Autodesk Fusion 360 part; units mm, degrees
(part 2 of 2)
sketch "Sketch14" plane through (0, 0, 2.5) normal (0, 0, 1) x (1, 0, 0)
  circle A0 centre (35, 68) radius 2.5
  line L0 (125, 20) -> (125, 40)
  line L1 (125, 40) -> (145, 40)
  line L2 (145, 40) -> (145, 20)
  line L3 (145, 20) -> (125, 20)
  line L4 (9.0092, 116.9631) -> (-2, 103.2016)
  line L5 (-2, 103.2016) -> (-2, 11.7984)
  line L6 (-2, 11.7984) -> (9.0388, -2)
  line L7 (9.0388, -2) -> (145.9612, -2)
  line L8 (145.9612, -2) -> (157, 11.7984)
  line L9 (157, 11.7984) -> (157, 103.2016)
  line L10 (157, 103.2016) -> (145.9908, 116.9631)
  spline S0 degree 3 poles (145.9908, 116.9631) (145.6863, 116.9749) (145.3819, 116.9867) (145.0774, 116.9985) (138.5067, 117.2531) (133.3735, 117.448) (128.9839, 117.6117) (123.3639, 117.8212) (118.9847, 117.9786) (115.2269, 118.109) (110.0914, 118.2873) (106.1355, 118.4146) (102.7172, 118.5165) (98.1859, 118.6516) (94.6262, 118.7412) (91.4483, 118.8069) (86.738, 118.9044) (82.8964, 118.9491) (79.1064, 118.9596) (75.4974, 118.9695) (71.9821, 118.9477) (67.9652, 118.8866) (65.0372, 118.8421) (61.8549, 118.7768) (57.9877, 118.6763) (54.9693, 118.5979) (51.5444, 118.4985) (47.2448, 118.3599) (43.8313, 118.2498) (39.8791, 118.1155) (34.8319, 117.9345) (31.2439, 117.8059) (27.106, 117.6538) (21.9652, 117.4597) (18.5002, 117.3289) (14.5782, 117.1789) (9.9226, 116.9985) (9.6181, 116.9867) (9.3137, 116.9749) (9.0092, 116.9631) knots -13.536157 -13.536157 -13.536157 -13.536157 -13.5057 -13.5057 -13.5057 -12.848427 -12.848427 -12.848427 -12.006919 -12.006919 -12.006919 -10.856885 -10.856885 -10.856885 -9.332387 -9.332387 -9.332387 -7.072806 -7.072806 -7.072806 -4.921137 -4.921137 -4.921137 -3.352707 -3.352707 -3.352707 -2.128529 -2.128529 -2.128529 -1.156627 -1.156627 -1.156627 -0.465703 -0.465703 -0.465703 0 0 0 0.030457 0.030457 0.030457 0.030457
  line L11 (-1, 83.2016) -> (0.5, 83.2016)
  line L12 (0.5, 83.2016) -> (0.5, 75.2016)
  line L13 (0.5, 75.2016) -> (-1, 75.2016)
  line L14 (-1, 75.2016) -> (-1, 83.2016)
  line L15 (-1, 39.7984) -> (0.5, 39.7984)
  line L16 (0.5, 39.7984) -> (0.5, 31.7984)
  line L17 (0.5, 31.7984) -> (-1, 31.7984)
  line L18 (-1, 31.7984) -> (-1, 39.7984)
  line L19 (77.5, -2) -> (77.5, 118.9618) construction
  line L20 (156, 83.2016) -> (154.5, 83.2016)
  line L21 (154.5, 39.7984) -> (154.5, 31.7984)
  line L22 (154.5, 83.2016) -> (154.5, 75.2016)
  line L23 (154.5, 75.2016) -> (156, 75.2016)
  line L24 (156, 39.7984) -> (154.5, 39.7984)
  line L25 (156, 75.2016) -> (156, 83.2016)
  line L26 (154.5, 31.7984) -> (156, 31.7984)
  line L27 (156, 31.7984) -> (156, 39.7984)
  point P0 (157, 11.7984)
  dimension "d137" = 1.5
  dimension "d138" = 8
  dimension "d139" = 1
  dimension "d140" = 1
  dimension "d141" = 20
  dimension "d142" = 20
  dimension "d143" = 8
  dimension "d144" = 1.5
  constraint horizontal L11
  constraint vertical L12
  constraint horizontal L13
  constraint vertical L14
  constraint horizontal L15
  constraint vertical L16
  constraint horizontal L17
  constraint vertical L18
  constraint midpoint L7 L19.start
  constraint coincident S0 L19.end
  constraint perpendicular L7 L19
  constraint symmetric L5.end L19 P0
  constraint symmetric L11.start L19 L20.start
  constraint symmetric L11.end L19 L20.end
  constraint symmetric L12.end L19 L22.end
  constraint symmetric L13.end L19 L23.end
  constraint symmetric L15.start L19 L24.start
  constraint symmetric L15.end L19 L21.start
  constraint symmetric L16.end L19 L21.end
  constraint symmetric L17.end L19 L26.end
  measures "d137" distance of L15.start L15.end
  measures "d138" distance of L15.start L17.end
  measures "d139" distance of L5 L18
  measures "d140" distance of L5 L14
  measures "d141" vertical distance of L5.end L17.end
  measures "d142" vertical distance of L4.end L11.start
  measures "d143" distance of L11.start L13.end
  measures "d144" distance of L12.end L13.end
extrude "Extrude17" add sketch "Sketch14" along normal blind 8 contours L11 L12 L13 L14 | L15 L16 L17 L18 | L20 L22 L23 L25 | L21 L24 L26 L27
fillet "Fillet1" radius 0.5 16 edges at (-1, 83.2016, 6.5) (0.5, 83.2016, 6.5) (-1, 75.2016, 6.5) (0.5, 75.2016, 6.5) (0.5, 39.7984, 6.5) (-1, 39.7984, 6.5) (-1, 31.7984, 6.5) (0.5, 31.7984, 6.5) (154.5, 83.2016, 6.5) (156, 83.2016, 6.5) (154.5, 75.2016, 6.5) (156, 75.2016, 6.5) (156, 31.7984, 6.5) (154.5, 31.7984, 6.5) (156, 39.7984, 6.5) (154.5, 39.7984, 6.5)
equation "d7 = ( ( 155 - 135 ) / 2 ) * 1 mm"
equation "d29 = ( 35 / 2 ) * 1 mm"
equation "d31 = ( 45 / 2 ) * 1 mm"
equation "d35 = -25 mm + 2 mm"
equation "d56 = ( 66.4 / 2 ) * 1 mm"
equation "d64 = ( 66.4 / 2 ) * 1 mm"
equation "d83 = ( ( 51 + 38 ) / 2 ) * 1 mm"
